Autodesk Fusion 360 part; units mm, degrees
(part 2 of 2)
  line L439 (42.9149, -28.0117) -> (44.5155, -27.6715)
  line L440 (44.5155, -27.6715) -> (44.4279, -27.1608)
  line L441 (44.4279, -27.1608) -> (44.4111, -26.8014)
  line L442 (44.4111, -26.8014) -> (44.4316, -26.4359)
  line L443 (44.4316, -26.4359) -> (44.4774, -26.0666)
  line L444 (44.4774, -26.0666) -> (44.5447, -25.6945)
  line L445 (44.5447, -25.6945) -> (44.6313, -25.3202)
  line L446 (44.6313, -25.3202) -> (44.7358, -24.9442)
  line L447 (44.7358, -24.9442) -> (44.8572, -24.5669)
  line L448 (44.8572, -24.5669) -> (44.9949, -24.1889)
  line L449 (44.9949, -24.1889) -> (45.9888, -24.0844)
  line L450 (45.9888, -24.0844) -> (46.2021, -24.4256)
  line L451 (46.2021, -24.4256) -> (46.3993, -24.7693)
  line L452 (46.3993, -24.7693) -> (46.5797, -25.1154)
  line L453 (46.5797, -25.1154) -> (46.7422, -25.4635)
  line L454 (46.7422, -25.4635) -> (46.8854, -25.8136)
  line L455 (46.8854, -25.8136) -> (47.007, -26.1653)
  line L456 (47.007, -26.1653) -> (47.103, -26.5185)
  line L457 (47.103, -26.5185) -> (47.1613, -26.8736)
  line L458 (47.1613, -26.8736) -> (47.1819, -27.3912)
  line L459 (47.1819, -27.3912) -> (48.8181, -27.3912)
  line L460 (48.8181, -27.3912) -> (48.8387, -26.8736)
  line L461 (48.8387, -26.8736) -> (48.897, -26.5185)
  line L462 (48.897, -26.5185) -> (48.993, -26.1653)
  line L463 (48.993, -26.1653) -> (49.1146, -25.8136)
  line L464 (49.1146, -25.8136) -> (49.2578, -25.4635)
  line L465 (49.2578, -25.4635) -> (49.4203, -25.1154)
  line L466 (49.4203, -25.1154) -> (49.6007, -24.7693)
  line L467 (49.6007, -24.7693) -> (49.7979, -24.4256)
  line L468 (49.7979, -24.4256) -> (50.0112, -24.0844)
  line L469 (50.0112, -24.0844) -> (51.0051, -24.1889)
  line L470 (51.0051, -24.1889) -> (51.1428, -24.5669)
  line L471 (51.1428, -24.5669) -> (51.2642, -24.9442)
  line L472 (51.2642, -24.9442) -> (51.3687, -25.3202)
  line L473 (51.3687, -25.3202) -> (51.4553, -25.6945)
  line L474 (51.4553, -25.6945) -> (51.5226, -26.0666)
  line L475 (51.5226, -26.0666) -> (51.5684, -26.4359)
  line L476 (51.5684, -26.4359) -> (51.5889, -26.8014)
  line L477 (51.5889, -26.8014) -> (51.5721, -27.1608)
  line L478 (51.5721, -27.1608) -> (51.4845, -27.6715)
  line L479 (51.4845, -27.6715) -> (53.0851, -28.0117)
  line L480 (53.0851, -28.0117) -> (53.2128, -27.5096)
  line L481 (53.2128, -27.5096) -> (53.3436, -27.1744)
  line L482 (53.3436, -27.1744) -> (53.511, -26.8488)
  line L483 (53.511, -26.8488) -> (53.703, -26.5301)
  line L484 (53.703, -26.5301) -> (53.9159, -26.2175)
  line L485 (53.9159, -26.2175) -> (54.1473, -25.9108)
  line L486 (54.1473, -25.9108) -> (54.3957, -25.6098)
  line L487 (54.3957, -25.6098) -> (54.66, -25.3145)
  line L488 (54.66, -25.3145) -> (54.9396, -25.0252)
  line L489 (54.9396, -25.0252) -> (55.89, -25.334)
  line L490 (55.89, -25.334) -> (55.9461, -25.7324)
  line L491 (55.9461, -25.7324) -> (55.9864, -26.1266)
  line L492 (55.9864, -26.1266) -> (56.0105, -26.5162)
  line L493 (56.0105, -26.5162) -> (56.0174, -26.9003)
  line L494 (56.0174, -26.9003) -> (56.0058, -27.2783)
  line L495 (56.0058, -27.2783) -> (55.9739, -27.6491)
  line L496 (55.9739, -27.6491) -> (55.9179, -28.0109)
  line L497 (55.9179, -28.0109) -> (55.8267, -28.3589)
  line L498 (55.8267, -28.3589) -> (55.6349, -28.8402)
  line L499 (55.6349, -28.8402) -> (57.1297, -29.5057)
  line L500 (57.1297, -29.5057) -> (57.3591, -29.0412)
  line L501 (57.3591, -29.0412) -> (57.5567, -28.7405)
  line L502 (57.5567, -28.7405) -> (57.7881, -28.4568)
  line L503 (57.7881, -28.4568) -> (58.0423, -28.185)
  line L504 (58.0423, -28.185) -> (58.3154, -27.9235)
  line L505 (58.3154, -27.9235) -> (58.6055, -27.6716)
  line L506 (58.6055, -27.6716) -> (58.9111, -27.4288)
  line L507 (58.9111, -27.4288) -> (59.2311, -27.195)
  line L508 (59.2311, -27.195) -> (59.5647, -26.9701)
  line L509 (59.5647, -26.9701) -> (60.4301, -27.4697)
  line L510 (60.4301, -27.4697) -> (60.4021, -27.8711)
  line L511 (60.4021, -27.8711) -> (60.3597, -28.2651)
  line L512 (60.3597, -28.2651) -> (60.3022, -28.6511)
  line L513 (60.3022, -28.6511) -> (60.229, -29.0283)
  line L514 (60.229, -29.0283) -> (60.1392, -29.3957)
  line L515 (60.1392, -29.3957) -> (60.0308, -29.7517)
  line L516 (60.0308, -29.7517) -> (59.9008, -30.0939)
  line L517 (59.9008, -30.0939) -> (59.7393, -30.4154)
  line L518 (59.7393, -30.4154) -> (59.4516, -30.8463)
  line L519 (59.4516, -30.8463) -> (60.7754, -31.808)
  line L520 (60.7754, -31.808) -> (61.0963, -31.4013)
  line L521 (61.0963, -31.4013) -> (61.3522, -31.1483)
  line L522 (61.3522, -31.1483) -> (61.6375, -30.919)
  line L523 (61.6375, -30.919) -> (61.9426, -30.7059)
  line L524 (61.9426, -30.7059) -> (62.2642, -30.5069)
  line L525 (62.2642, -30.5069) -> (62.6003, -30.3208)
  line L526 (62.6003, -30.3208) -> (62.9497, -30.1469)
  line L527 (62.9497, -30.1469) -> (63.3113, -29.9847)
  line L528 (63.3113, -29.9847) -> (63.6843, -29.834)
  line L529 (63.6843, -29.834) -> (64.427, -30.5027)
  line L530 (64.427, -30.5027) -> (64.3162, -30.8895)
  line L531 (64.3162, -30.8895) -> (64.1927, -31.2661)
  line L532 (64.1927, -31.2661) -> (64.0562, -31.6317)
  line L533 (64.0562, -31.6317) -> (63.9062, -31.9854)
  line L534 (63.9062, -31.9854) -> (63.7419, -32.3261)
  line L535 (63.7419, -32.3261) -> (63.562, -32.6518)
  line L536 (63.562, -32.6518) -> (63.3637, -32.9595)
  line L537 (63.3637, -32.9595) -> (63.1388, -33.2404)
  line L538 (63.1388, -33.2404) -> (62.7679, -33.602)
  line L539 (62.7679, -33.602) -> (63.8627, -34.818)
  line L540 (63.8627, -34.818) -> (64.2612, -34.4869)
  line L541 (64.2612, -34.4869) -> (64.564, -34.2927)
  line L542 (64.564, -34.2927) -> (64.8908, -34.1276)
  line L543 (64.8908, -34.1276) -> (65.2335, -33.9827)
  line L544 (65.2335, -33.9827) -> (65.5895, -33.8549)
  line L545 (65.5895, -33.8549) -> (65.957, -33.7427)
  line L546 (65.957, -33.7427) -> (66.3349, -33.6452)
  line L547 (66.3349, -33.6452) -> (66.7223, -33.5618)
  line L548 (66.7223, -33.5618) -> (67.1185, -33.492)
  line L549 (67.1185, -33.492) -> (67.7059, -34.3005)
  line L550 (67.7059, -34.3005) -> (67.5171, -34.6557)
  line L551 (67.5171, -34.6557) -> (67.318, -34.9984)
  line L552 (67.318, -34.9984) -> (67.1085, -35.3277)
  line L553 (67.1085, -35.3277) -> (66.8883, -35.6425)
  line L554 (66.8883, -35.6425) -> (66.6567, -35.9415)
  line L555 (66.6567, -35.9415) -> (66.413, -36.2227)
  line L556 (66.413, -36.2227) -> (66.155, -36.4825)
  line L557 (66.155, -36.4825) -> (65.8767, -36.7105)
  line L558 (65.8767, -36.7105) -> (65.4386, -36.9871)
  line L559 (65.4386, -36.9871) -> (66.2568, -38.4041)
  line L560 (66.2568, -38.4041) -> (66.7154, -38.1631)
  line L561 (66.7154, -38.1631) -> (67.052, -38.0361)
  line L562 (67.052, -38.0361) -> (67.4059, -37.9425)
  line L563 (67.4059, -37.9425) -> (67.7713, -37.872)
  line L564 (67.7713, -37.872) -> (68.146, -37.821)
  line L565 (68.146, -37.821) -> (68.5288, -37.7877)
  line L566 (68.5288, -37.7877) -> (68.9187, -37.7709)
  line L567 (68.9187, -37.7709) -> (69.315, -37.7698)
  line L568 (69.315, -37.7698) -> (69.7171, -37.784)
  line L569 (69.7171, -37.784) -> (70.1236, -38.6969)
  line L570 (70.1236, -38.6969) -> (69.865, -39.0052)
  line L571 (69.865, -39.0052) -> (69.599, -39.299)
  line L572 (69.599, -39.299) -> (69.3257, -39.5775)
  line L573 (69.3257, -39.5775) -> (69.0448, -39.8396)
  line L574 (69.0448, -39.8396) -> (68.7561, -40.084)
  line L575 (68.7561, -40.084) -> (68.4592, -40.3083)
  line L576 (68.4592, -40.3083) -> (68.1529, -40.5088)
  line L577 (68.1529, -40.5088) -> (67.8333, -40.6739)
  line L578 (67.8333, -40.6739) -> (67.3473, -40.8534)
  line L579 (67.3473, -40.8534) -> (67.8529, -42.4096)
  line L580 (67.8529, -42.4096) -> (68.3516, -42.2692)
  line L581 (68.3516, -42.2692) -> (68.7073, -42.2149)
  line L582 (68.7073, -42.2149) -> (69.0729, -42.197)
  line L583 (69.0729, -42.197) -> (69.445, -42.204)
  line L584 (69.445, -42.204) -> (69.8221, -42.2321)
  line L585 (69.8221, -42.2321) -> (70.2035, -42.2791)
  line L586 (70.2035, -42.2791) -> (70.5883, -42.3437)
  line L587 (70.5883, -42.3437) -> (70.9762, -42.425)
  line L588 (70.9762, -42.425) -> (71.3666, -42.5224)
  line L589 (71.3666, -42.5224) -> (71.5743, -43.5)
  line L590 (71.5743, -43.5) -> (71.2573, -43.7477)
  line L591 (71.2573, -43.7477) -> (70.9361, -43.9798)
  line L592 (70.9361, -43.9798) -> (70.6108, -44.1954)
  line L593 (70.6108, -44.1954) -> (70.2815, -44.3934)
  line L594 (70.2815, -44.3934) -> (69.9484, -44.5724)
  line L595 (69.9484, -44.5724) -> (69.6113, -44.7301)
  line L596 (69.6113, -44.7301) -> (69.27, -44.8625)
  line L597 (69.27, -44.8625) -> (68.923, -44.9576)
  line L598 (68.923, -44.9576) -> (68.4104, -45.0321)
  line L599 (68.4104, -45.0321) -> (68.5814, -46.6595)
extrude "Extrude8'" add sketch "Sketch8 (2)" along normal mid plane 6 bodies 3 in component "Drive roller"
ref_plane "WorkPlane9" through (0, 114.25, 0) normal (0, 1, 0) x (0, 0, 1) in component "Drive roller"
sketch "Sketch9 (2)" plane through (0, 114.25, 0) normal (0, 1, 0) x (1, 0, 0) in component "Drive roller"
  circle A0 centre (68, -48) radius 1.3
extrude "Extrude9'" cut sketch "Sketch9 (2)" along normal mid plane 10.5 bodies 3 in component "Drive roller"
ref_plane "WorkPlane10" through (0, 114.25, 0) normal (0, 1, 0) x (0, 0, 1) in component "Drive roller"
sketch "Sketch10 (2)" plane through (0, 114.25, 0) normal (0, 1, 0) x (1, 0, 0) in component "Drive roller"
  circle A0 centre (48, -68) radius 1.3
extrude "Extrude10'" cut sketch "Sketch10 (2)" along normal mid plane 10.5 bodies 3 in component "Drive roller"
ref_plane "WorkPlane11" through (0, 114.25, 0) normal (0, 1, 0) x (0, 0, 1) in component "Drive roller"
sketch "Sketch11 (2)" plane through (0, 114.25, 0) normal (0, 1, 0) x (1, 0, 0) in component "Drive roller"
  circle A0 centre (28, -48) radius 1.3
extrude "Extrude11'" cut sketch "Sketch11 (2)" along normal mid plane 10.5 bodies 3 in component "Drive roller"
ref_plane "WorkPlane12" through (0, 114.25, 0) normal (0, 1, 0) x (0, 0, 1) in component "Drive roller"
sketch "Sketch12 (2)" plane through (0, 114.25, 0) normal (0, 1, 0) x (1, 0, 0) in component "Drive roller"
  circle A0 centre (48, -28) radius 1.3
extrude "Extrude12'" cut sketch "Sketch12 (2)" along normal mid plane 10.5 bodies 3 in component "Drive roller"
ref_plane "WorkPlane1" through (0, 72, 0) normal (0, 1, 0) x (0, 0, 1) in component "Idle roller"
sketch "Sketch1 (3)" plane through (0, 72, 0) normal (0, 1, 0) x (1, 0, 0) in component "Idle roller"
  circle A0 centre (360, -48) radius 30
extrude "Extrude1''" add sketch "Sketch1 (3)" along normal mid plane 88 separate body makes body 4 in component "Idle roller"
ref_plane "WorkPlane2" through (0, 26.5, 0) normal (0, 1, 0) x (0, 0, 1) in component "Idle roller"
sketch "Sketch2 (3)" plane through (0, 26.5, 0) normal (0, 1, 0) x (1, 0, 0) in component "Idle roller"
  circle A0 centre (360, -48) radius 33
extrude "Extrude2''" add sketch "Sketch2 (3)" along normal mid plane 3 bodies 4 in component "Idle roller"
ref_plane "WorkPlane3" through (0, 117.5, 0) normal (0, 1, 0) x (0, 0, 1) in component "Idle roller"
sketch "Sketch3 (3)" plane through (0, 117.5, 0) normal (0, 1, 0) x (1, 0, 0) in component "Idle roller"
  circle A0 centre (360, -48) radius 33
extrude "Extrude3''" add sketch "Sketch3 (3)" along normal mid plane 3 bodies 4 in component "Idle roller"
ref_plane "WorkPlane4" through (0, 128.75, 0) normal (0, 1, 0) x (0, 0, 1) in component "Idle roller"
sketch "Sketch4 (3)" plane through (0, 128.75, 0) normal (0, 1, 0) x (1, 0, 0) in component "Idle roller"
  circle A0 centre (360, -48) radius 8
extrude "Extrude4''" add sketch "Sketch4 (3)" along normal mid plane 19.5 bodies 4 in component "Idle roller"
ref_plane "WorkPlane5" through (0, 141, 0) normal (0, 1, 0) x (0, 0, 1) in component "Idle roller"
sketch "Sketch5 (3)" plane through (0, 141, 0) normal (0, 1, 0) x (1, 0, 0) in component "Idle roller"
  circle A0 centre (360, -48) radius 4
extrude "Extrude5''" add sketch "Sketch5 (3)" along normal mid plane 5 bodies 4 in component "Idle roller"
ref_plane "WorkPlane6" through (0, 15.25, 0) normal (0, 1, 0) x (0, 0, 1) in component "Idle roller"
sketch "Sketch6 (3)" plane through (0, 15.25, 0) normal (0, 1, 0) x (1, 0, 0) in component "Idle roller"
  circle A0 centre (360, -48) radius 8
extrude "Extrude6''" add sketch "Sketch6 (3)" along normal mid plane 19.5 bodies 4 in component "Idle roller"
ref_plane "WorkPlane7" through (0, 3, 0) normal (0, 1, 0) x (0, 0, 1) in component "Idle roller"
sketch "Sketch7 (3)" plane through (0, 3, 0) normal (0, 1, 0) x (1, 0, 0) in component "Idle roller"
  circle A0 centre (360, -48) radius 4
extrude "Extrude7''" add sketch "Sketch7 (3)" along normal mid plane 5 bodies 4 in component "Idle roller"
ref_plane "WorkPlane1" through (0, -4.5, 0) normal (0, 1, 0) x (0, 0, 1) in component "Pinion"
sketch "Sketch1 (4)" plane through (0, -4.5, 0) normal (0, 1, 0) x (1, 0, 0) in component "Pinion"
  line L0 (91.0629, -46.9226) -> (92.2515, -46.7851)
  line L1 (92.2515, -46.7851) -> (92.5267, -46.7953)
  line L2 (92.5267, -46.7953) -> (92.8056, -46.8416)
  line L3 (92.8056, -46.8416) -> (93.0865, -46.913)
  line L4 (93.0865, -46.913) -> (93.3683, -47.006)
  line L5 (93.3683, -47.006) -> (93.6505, -47.1186)
  line L6 (93.6505, -47.1186) -> (93.9323, -47.2498)
  line L7 (93.9323, -47.2498) -> (94.2132, -47.3986)
  line L8 (94.2132, -47.3986) -> (94.4926, -47.5645)
  line L9 (94.4926, -47.5645) -> (94.4926, -48.4355)
  line L10 (94.4926, -48.4355) -> (94.2132, -48.6014)
  line L11 (94.2132, -48.6014) -> (93.9323, -48.7502)
  line L12 (93.9323, -48.7502) -> (93.6505, -48.8814)
  line L13 (93.6505, -48.8814) -> (93.3683, -48.994)
  line L14 (93.3683, -48.994) -> (93.0865, -49.087)
  line L15 (93.0865, -49.087) -> (92.8056, -49.1584)
  line L16 (92.8056, -49.1584) -> (92.5267, -49.2047)
  line L17 (92.5267, -49.2047) -> (92.2515, -49.2149)
  line L18 (92.2515, -49.2149) -> (91.0629, -49.0774)
  line L19 (91.0629, -49.0774) -> (90.696, -50.8036)
  line L20 (90.696, -50.8036) -> (91.8378, -51.1614)
  line L21 (91.8378, -51.1614) -> (92.085, -51.2827)
  line L22 (92.085, -51.2827) -> (92.321, -51.4384)
  line L23 (92.321, -51.4384) -> (92.5485, -51.6179)
  line L24 (92.5485, -51.6179) -> (92.7682, -51.8175)
  line L25 (92.7682, -51.8175) -> (92.9801, -52.0352)
  line L26 (92.9801, -52.0352) -> (93.1842, -52.2697)
  line L27 (93.1842, -52.2697) -> (93.3803, -52.5198)
  line L28 (93.3803, -52.5198) -> (93.5681, -52.785)
  line L29 (93.5681, -52.785) -> (93.2138, -53.5808)
  line L30 (93.2138, -53.5808) -> (92.8911, -53.6186)
  line L31 (92.8911, -53.6186) -> (92.574, -53.6403)
  line L32 (92.574, -53.6403) -> (92.2632, -53.6455)
  line L33 (92.2632, -53.6455) -> (91.9596, -53.6337)
  line L34 (91.9596, -53.6337) -> (91.6642, -53.604)
  line L35 (91.6642, -53.604) -> (91.3786, -53.555)
  line L36 (91.3786, -53.555) -> (91.105, -53.4838)
  line L37 (91.105, -53.4838) -> (90.8494, -53.3812)
  line L38 (90.8494, -53.3812) -> (89.8195, -52.7722)
  line L39 (89.8195, -52.7722) -> (88.7822, -54.1999)
  line L40 (88.7822, -54.1999) -> (89.6797, -54.9912)
  line L41 (89.6797, -54.9912) -> (89.8563, -55.2026)
  line L42 (89.8563, -55.2026) -> (90.0086, -55.4408)
  line L43 (90.0086, -55.4408) -> (90.1434, -55.6973)
  line L44 (90.1434, -55.6973) -> (90.2629, -55.969)
  line L45 (90.2629, -55.969) -> (90.368, -56.254)
  line L46 (90.368, -56.254) -> (90.4591, -56.5512)
  line L47 (90.4591, -56.5512) -> (90.5364, -56.8596)
  line L48 (90.5364, -56.8596) -> (90.6001, -57.1781)
  line L49 (90.6001, -57.1781) -> (89.9528, -57.761)
  line L50 (89.9528, -57.761) -> (89.6426, -57.6644)
  line L51 (89.6426, -57.6644) -> (89.3441, -57.5552)
  line L52 (89.3441, -57.5552) -> (89.058, -57.4335)
  line L53 (89.058, -57.4335) -> (88.7855, -57.2992)
  line L54 (88.7855, -57.2992) -> (88.5278, -57.152)
  line L55 (88.5278, -57.152) -> (88.2868, -56.9911)
  line L56 (88.2868, -56.9911) -> (88.0658, -56.8148)
  line L57 (88.0658, -56.8148) -> (87.874, -56.6171)
  line L58 (87.874, -56.6171) -> (87.1809, -55.6418)
  line L59 (87.1809, -55.6418) -> (85.6525, -56.5241)
  line L60 (85.6525, -56.5241) -> (86.1506, -57.6121)
  line L61 (86.1506, -57.6121) -> (86.2259, -57.877)
  line L62 (86.2259, -57.877) -> (86.2681, -58.1565)
  line L63 (86.2681, -58.1565) -> (86.287, -58.4457)
  line L64 (86.287, -58.4457) -> (86.2856, -58.7425)
  line L65 (86.2856, -58.7425) -> (86.2657, -59.0457)
  line L66 (86.2657, -59.0457) -> (86.228, -59.3542)
  line L67 (86.228, -59.3542) -> (86.1733, -59.6674)
  line L68 (86.1733, -59.6674) -> (86.1019, -59.9843)
  line L69 (86.1019, -59.9843) -> (85.2734, -60.2535)
  line L70 (85.2734, -60.2535) -> (85.0294, -60.039)
  line L71 (85.0294, -60.039) -> (84.8011, -59.8179)
  line L72 (84.8011, -59.8179) -> (84.5892, -59.5904)
  line L73 (84.5892, -59.5904) -> (84.3949, -59.3569)
  line L74 (84.3949, -59.3569) -> (84.2193, -59.1175)
  line L75 (84.2193, -59.1175) -> (84.0646, -58.8725)
  line L76 (84.0646, -58.8725) -> (83.9344, -58.6215)
  line L77 (83.9344, -58.6215) -> (83.8397, -58.363)
  line L78 (83.8397, -58.363) -> (83.6031, -57.19)
  line L79 (83.6031, -57.19) -> (81.8481, -57.3745)
  line L80 (81.8481, -57.3745) -> (81.8606, -58.571)
  line L81 (81.8606, -58.571) -> (81.8216, -58.8436)
  line L82 (81.8216, -58.8436) -> (81.7465, -59.1162)
  line L83 (81.7465, -59.1162) -> (81.6461, -59.388)
  line L84 (81.6461, -59.388) -> (81.5241, -59.6586)
  line L85 (81.5241, -59.6586) -> (81.3826, -59.9274)
  line L86 (81.3826, -59.9274) -> (81.2227, -60.194)
  line L87 (81.2227, -60.194) -> (81.0453, -60.4578)
  line L88 (81.0453, -60.4578) -> (80.8512, -60.7183)
  line L89 (80.8512, -60.7183) -> (79.9849, -60.6272)
  line L90 (79.9849, -60.6272) -> (79.8492, -60.3321)
  line L91 (79.8492, -60.3321) -> (79.7305, -60.0372)
  line L92 (79.7305, -60.0372) -> (79.6295, -59.7432)
  line L93 (79.6295, -59.7432) -> (79.547, -59.4508)
  line L94 (79.547, -59.4508) -> (79.4839, -59.1607)
  line L95 (79.4839, -59.1607) -> (79.4423, -58.874)
  line L96 (79.4423, -58.874) -> (79.4254, -58.5918)
  line L97 (79.4254, -58.5918) -> (79.444, -58.317)
  line L98 (79.444, -58.317) -> (79.705, -57.1492)
  line L99 (79.705, -57.1492) -> (78.0266, -56.6039)
  line L100 (78.0266, -56.6039) -> (77.5514, -57.702)
  line L101 (77.5514, -57.702) -> (77.405, -57.9353)
  line L102 (77.405, -57.9353) -> (77.2254, -58.1537)
  line L103 (77.2254, -58.1537) -> (77.0232, -58.3612)
  line L104 (77.0232, -58.3612) -> (76.8017, -58.5588)
  line L105 (76.8017, -58.5588) -> (76.563, -58.7468)
  line L106 (76.563, -58.7468) -> (76.3085, -58.9253)
  line L107 (76.3085, -58.9253) -> (76.0392, -59.0941)
  line L108 (76.0392, -59.0941) -> (75.7559, -59.2532)
  line L109 (75.7559, -59.2532) -> (75.0015, -58.8176)
  line L110 (75.0015, -58.8176) -> (74.9976, -58.4927)
  line L111 (74.9976, -58.4927) -> (75.0092, -58.1751)
  line L112 (75.0092, -58.1751) -> (75.0365, -57.8654)
  line L113 (75.0365, -57.8654) -> (75.08, -57.5647)
  line L114 (75.08, -57.5647) -> (75.1404, -57.2742)
  line L115 (75.1404, -57.2742) -> (75.2189, -56.9952)
  line L116 (75.2189, -56.9952) -> (75.3183, -56.7306)
  line L117 (75.3183, -56.7306) -> (75.4471, -56.4871)
  line L118 (75.4471, -56.4871) -> (76.1605, -55.5265)
  line L119 (76.1605, -55.5265) -> (74.849, -54.3456)
  line L120 (74.849, -54.3456) -> (73.9682, -55.1555)
  line L121 (73.9682, -55.1555) -> (73.7396, -55.309)
  line L122 (73.7396, -55.309) -> (73.4867, -55.4355)
  line L123 (73.4867, -55.4355) -> (73.2175, -55.5428)
  line L124 (73.2175, -55.5428) -> (72.9349, -55.6333)
  line L125 (72.9349, -55.6333) -> (72.6404, -55.708)
  line L126 (72.6404, -55.708) -> (72.3353, -55.7675)
  line L127 (72.3353, -55.7675) -> (72.0206, -55.8122)
  line L128 (72.0206, -55.8122) -> (71.6971, -55.8422)
  line L129 (71.6971, -55.8422) -> (71.185, -55.1375)
  line L130 (71.185, -55.1375) -> (71.3136, -54.8391)
  line L131 (71.3136, -54.8391) -> (71.4534, -54.5537)
  line L132 (71.4534, -54.5537) -> (71.6043, -54.2819)
  line L133 (71.6043, -54.2819) -> (71.7663, -54.0249)
  line L134 (71.7663, -54.0249) -> (71.9397, -53.784)
  line L135 (71.9397, -53.784) -> (72.1249, -53.5611)
  line L136 (72.1249, -53.5611) -> (72.3233, -53.3598)
  line L137 (72.3233, -53.3598) -> (72.54, -53.1897)
  line L138 (72.54, -53.1897) -> (73.5824, -52.6023)
  line L139 (73.5824, -52.6023) -> (72.8646, -50.9901)
  line L140 (72.8646, -50.9901) -> (71.7306, -51.3718)
  line L141 (71.7306, -51.3718) -> (71.4592, -51.419)
  line L142 (71.4592, -51.419) -> (71.1768, -51.4317)
  line L143 (71.1768, -51.4317) -> (70.8873, -51.4203)
  line L144 (70.8873, -51.4203) -> (70.5922, -51.3879)
  line L145 (70.5922, -51.3879) -> (70.2928, -51.3363)
  line L146 (70.2928, -51.3363) -> (69.9899, -51.2666)
  line L147 (69.9899, -51.2666) -> (69.6842, -51.1795)
  line L148 (69.6842, -51.1795) -> (69.3765, -51.0754)
  line L149 (69.3765, -51.0754) -> (69.1953, -50.2233)
  line L150 (69.1953, -50.2233) -> (69.4341, -50.003)
  line L151 (69.4341, -50.003) -> (69.6779, -49.799)
  line L152 (69.6779, -49.799) -> (69.9263, -49.6122)
  line L153 (69.9263, -49.6122) -> (70.1789, -49.4433)
  line L154 (70.1789, -49.4433) -> (70.4353, -49.2937)
  line L155 (70.4353, -49.2937) -> (70.6951, -49.1655)
  line L156 (70.6951, -49.1655) -> (70.9583, -49.0622)
  line L157 (70.9583, -49.0622) -> (71.2254, -48.995)
  line L158 (71.2254, -48.995) -> (72.4166, -48.8824)
  line L159 (72.4166, -48.8824) -> (72.4166, -47.1176)
  line L160 (72.4166, -47.1176) -> (71.2254, -47.005)
  line L161 (71.2254, -47.005) -> (70.9583, -46.9378)
  line L162 (70.9583, -46.9378) -> (70.6951, -46.8345)
  line L163 (70.6951, -46.8345) -> (70.4353, -46.7063)
  line L164 (70.4353, -46.7063) -> (70.1789, -46.5567)
  line L165 (70.1789, -46.5567) -> (69.9263, -46.3878)
  line L166 (69.9263, -46.3878) -> (69.6779, -46.201)
  line L167 (69.6779, -46.201) -> (69.4341, -45.997)
  line L168 (69.4341, -45.997) -> (69.1953, -45.7767)
  line L169 (69.1953, -45.7767) -> (69.3765, -44.9246)
  line L170 (69.3765, -44.9246) -> (69.6842, -44.8205)
  line L171 (69.6842, -44.8205) -> (69.9899, -44.7334)
  line L172 (69.9899, -44.7334) -> (70.2928, -44.6637)
  line L173 (70.2928, -44.6637) -> (70.5922, -44.6121)
  line L174 (70.5922, -44.6121) -> (70.8873, -44.5797)
  line L175 (70.8873, -44.5797) -> (71.1768, -44.5683)
  line L176 (71.1768, -44.5683) -> (71.4592, -44.581)
  line L177 (71.4592, -44.581) -> (71.7306, -44.6282)
  line L178 (71.7306, -44.6282) -> (72.8646, -45.0099)
  line L179 (72.8646, -45.0099) -> (73.5824, -43.3977)
  line L180 (73.5824, -43.3977) -> (72.54, -42.8103)
  line L181 (72.54, -42.8103) -> (72.3233, -42.6402)
  line L182 (72.3233, -42.6402) -> (72.1249, -42.4389)
  line L183 (72.1249, -42.4389) -> (71.9397, -42.216)
  line L184 (71.9397, -42.216) -> (71.7663, -41.9751)
  line L185 (71.7663, -41.9751) -> (71.6043, -41.7181)
  line L186 (71.6043, -41.7181) -> (71.4534, -41.4463)
  line L187 (71.4534, -41.4463) -> (71.3136, -41.1609)
  line L188 (71.3136, -41.1609) -> (71.185, -40.8625)
  line L189 (71.185, -40.8625) -> (71.6971, -40.1578)
  line L190 (71.6971, -40.1578) -> (72.0206, -40.1878)
  line L191 (72.0206, -40.1878) -> (72.3353, -40.2325)
  line L192 (72.3353, -40.2325) -> (72.6404, -40.292)
  line L193 (72.6404, -40.292) -> (72.9349, -40.3667)
  line L194 (72.9349, -40.3667) -> (73.2175, -40.4572)
  line L195 (73.2175, -40.4572) -> (73.4867, -40.5645)
  line L196 (73.4867, -40.5645) -> (73.7396, -40.691)
  line L197 (73.7396, -40.691) -> (73.9682, -40.8445)
  line L198 (73.9682, -40.8445) -> (74.849, -41.6544)
  line L199 (74.849, -41.6544) -> (76.1605, -40.4735)
  line L200 (76.1605, -40.4735) -> (75.4471, -39.5129)
  line L201 (75.4471, -39.5129) -> (75.3183, -39.2694)
  line L202 (75.3183, -39.2694) -> (75.2189, -39.0048)
  line L203 (75.2189, -39.0048) -> (75.1404, -38.7258)
  line L204 (75.1404, -38.7258) -> (75.08, -38.4353)
  line L205 (75.08, -38.4353) -> (75.0365, -38.1346)
  line L206 (75.0365, -38.1346) -> (75.0092, -37.8249)
  line L207 (75.0092, -37.8249) -> (74.9976, -37.5073)
  line L208 (74.9976, -37.5073) -> (75.0015, -37.1824)
  line L209 (75.0015, -37.1824) -> (75.7559, -36.7468)
  line L210 (75.7559, -36.7468) -> (76.0392, -36.9059)
  line L211 (76.0392, -36.9059) -> (76.3085, -37.0747)
  line L212 (76.3085, -37.0747) -> (76.563, -37.2532)
  line L213 (76.563, -37.2532) -> (76.8017, -37.4412)
  line L214 (76.8017, -37.4412) -> (77.0232, -37.6388)
  line L215 (77.0232, -37.6388) -> (77.2254, -37.8463)
  line L216 (77.2254, -37.8463) -> (77.405, -38.0647)
  line L217 (77.405, -38.0647) -> (77.5514, -38.298)
  line L218 (77.5514, -38.298) -> (78.0266, -39.3961)
  line L219 (78.0266, -39.3961) -> (79.705, -38.8508)
  line L220 (79.705, -38.8508) -> (79.444, -37.683)
  line L221 (79.444, -37.683) -> (79.4254, -37.4082)
  line L222 (79.4254, -37.4082) -> (79.4423, -37.126)
  line L223 (79.4423, -37.126) -> (79.4839, -36.8393)
  line L224 (79.4839, -36.8393) -> (79.547, -36.5492)
  line L225 (79.547, -36.5492) -> (79.6295, -36.2568)
  line L226 (79.6295, -36.2568) -> (79.7305, -35.9628)
  line L227 (79.7305, -35.9628) -> (79.8492, -35.6679)
  line L228 (79.8492, -35.6679) -> (79.9849, -35.3728)
  line L229 (79.9849, -35.3728) -> (80.8512, -35.2817)
  line L230 (80.8512, -35.2817) -> (81.0453, -35.5422)
  line L231 (81.0453, -35.5422) -> (81.2227, -35.806)
  line L232 (81.2227, -35.806) -> (81.3826, -36.0726)
  line L233 (81.3826, -36.0726) -> (81.5241, -36.3414)
  line L234 (81.5241, -36.3414) -> (81.6461, -36.612)
  line L235 (81.6461, -36.612) -> (81.7465, -36.8838)
  line L236 (81.7465, -36.8838) -> (81.8216, -37.1564)
  line L237 (81.8216, -37.1564) -> (81.8606, -37.429)
  line L238 (81.8606, -37.429) -> (81.8481, -38.6255)
  line L239 (81.8481, -38.6255) -> (83.6031, -38.81)
  line L240 (83.6031, -38.81) -> (83.8397, -37.637)
  line L241 (83.8397, -37.637) -> (83.9344, -37.3785)
  line L242 (83.9344, -37.3785) -> (84.0646, -37.1275)
  line L243 (84.0646, -37.1275) -> (84.2193, -36.8825)
  line L244 (84.2193, -36.8825) -> (84.3949, -36.6431)
  line L245 (84.3949, -36.6431) -> (84.5892, -36.4096)
  line L246 (84.5892, -36.4096) -> (84.8011, -36.1821)
  line L247 (84.8011, -36.1821) -> (85.0294, -35.961)
  line L248 (85.0294, -35.961) -> (85.2734, -35.7465)
  line L249 (85.2734, -35.7465) -> (86.1019, -36.0157)
  line L250 (86.1019, -36.0157) -> (86.1733, -36.3326)
  line L251 (86.1733, -36.3326) -> (86.228, -36.6458)
  line L252 (86.228, -36.6458) -> (86.2657, -36.9543)
  line L253 (86.2657, -36.9543) -> (86.2856, -37.2575)
  line L254 (86.2856, -37.2575) -> (86.287, -37.5543)
  line L255 (86.287, -37.5543) -> (86.2681, -37.8435)
  line L256 (86.2681, -37.8435) -> (86.2259, -38.123)
  line L257 (86.2259, -38.123) -> (86.1506, -38.3879)
  line L258 (86.1506, -38.3879) -> (85.6525, -39.4759)
  line L259 (85.6525, -39.4759) -> (87.1809, -40.3582)
  line L260 (87.1809, -40.3582) -> (87.874, -39.3829)
  line L261 (87.874, -39.3829) -> (88.0658, -39.1852)
  line L262 (88.0658, -39.1852) -> (88.2868, -39.0089)
  line L263 (88.2868, -39.0089) -> (88.5278, -38.848)
  line L264 (88.5278, -38.848) -> (88.7855, -38.7008)
  line L265 (88.7855, -38.7008) -> (89.058, -38.5665)
  line L266 (89.058, -38.5665) -> (89.3441, -38.4448)
  line L267 (89.3441, -38.4448) -> (89.6426, -38.3356)
  line L268 (89.6426, -38.3356) -> (89.9528, -38.239)
  line L269 (89.9528, -38.239) -> (90.6001, -38.8219)
  line L270 (90.6001, -38.8219) -> (90.5364, -39.1404)
  line L271 (90.5364, -39.1404) -> (90.4591, -39.4488)
  line L272 (90.4591, -39.4488) -> (90.368, -39.746)
  line L273 (90.368, -39.746) -> (90.2629, -40.031)
  line L274 (90.2629, -40.031) -> (90.1434, -40.3027)
  line L275 (90.1434, -40.3027) -> (90.0086, -40.5592)
  line L276 (90.0086, -40.5592) -> (89.8563, -40.7974)
  line L277 (89.8563, -40.7974) -> (89.6797, -41.0088)
  line L278 (89.6797, -41.0088) -> (88.7822, -41.8001)
  line L279 (88.7822, -41.8001) -> (89.8195, -43.2278)
  line L280 (89.8195, -43.2278) -> (90.8494, -42.6188)
  line L281 (90.8494, -42.6188) -> (91.105, -42.5162)
  line L282 (91.105, -42.5162) -> (91.3786, -42.445)
  line L283 (91.3786, -42.445) -> (91.6642, -42.396)
  line L284 (91.6642, -42.396) -> (91.9596, -42.3663)
  line L285 (91.9596, -42.3663) -> (92.2632, -42.3545)
  line L286 (92.2632, -42.3545) -> (92.574, -42.3597)
  line L287 (92.574, -42.3597) -> (92.8911, -42.3814)
  line L288 (92.8911, -42.3814) -> (93.2138, -42.4192)
  line L289 (93.2138, -42.4192) -> (93.5681, -43.215)
  line L290 (93.5681, -43.215) -> (93.3803, -43.4802)
  line L291 (93.3803, -43.4802) -> (93.1842, -43.7303)
  line L292 (93.1842, -43.7303) -> (92.9801, -43.9648)
  line L293 (92.9801, -43.9648) -> (92.7682, -44.1825)
  line L294 (92.7682, -44.1825) -> (92.5485, -44.3821)
  line L295 (92.5485, -44.3821) -> (92.321, -44.5616)
  line L296 (92.321, -44.5616) -> (92.085, -44.7173)
  line L297 (92.085, -44.7173) -> (91.8378, -44.8386)
  line L298 (91.8378, -44.8386) -> (90.696, -45.1964)
  line L299 (90.696, -45.1964) -> (91.0629, -46.9226)
extrude "Extrude1'''" add sketch "Sketch1 (4)" along normal mid plane 6 separate body makes body 5 in component "Pinion"
ref_plane "WorkPlane2" through (0, -4.5, 0) normal (0, 1, 0) x (0, 0, 1) in component "Pinion"
sketch "Sketch2 (4)" plane through (0, -4.5, 0) normal (0, 1, 0) x (1, 0, 0) in component "Pinion"
  circle A0 centre (81.75, -48) radius 2.8
extrude "Extrude2'''" cut sketch "Sketch2 (4)" along normal mid plane 7 bodies 5 in component "Pinion"
ref_plane "WorkPlane3" through (0, -4.5, 0) normal (0, 1, 0) x (0, 0, 1) in component "Pinion"
sketch "Sketch3 (4)" plane through (0, -4.5, 0) normal (0, 1, 0) x (1, 0, 0) in component "Pinion"
  line L0 (78.65, -49.925) -> (84.85, -49.925)
  line L1 (84.85, -49.925) -> (84.85, -51.1)
  line L2 (84.85, -51.1) -> (78.65, -51.1)
  line L3 (78.65, -51.1) -> (78.65, -49.925)
extrude "Extrude3'''" add sketch "Sketch3 (4)" along normal mid plane 6 bodies 5 in component "Pinion"
ref_plane "WorkPlane4" through (0, -4.5, 0) normal (0, 1, 0) x (0, 0, 1) in component "Pinion"
sketch "Sketch4 (4)" plane through (0, -4.5, 0) normal (0, 1, 0) x (1, 0, 0) in component "Pinion"
  line L0 (78.65, -44.9) -> (84.85, -44.9)
  line L1 (84.85, -44.9) -> (84.85, -46.075)
  line L2 (84.85, -46.075) -> (78.65, -46.075)
  line L3 (78.65, -46.075) -> (78.65, -44.9)
extrude "Extrude4'''" add sketch "Sketch4 (4)" along normal mid plane 6 bodies 5 in component "Pinion"
ref_plane "WorkPlane1" through (0, 72, 0) normal (0, 1, 0) x (0, 0, 1) in component "Belt (reference)"
sketch "Sketch1 (5)" plane through (0, 72, 0) normal (0, 1, 0) x (1, 0, 0) in component "Belt (reference)"
  circle A0 centre (48, -48) radius 31
extrude "Extrude1''''" add sketch "Sketch1 (5)" along normal mid plane 80 separate body makes body 6 in component "Belt (reference)"
ref_plane "WorkPlane2" through (0, 72, 0) normal (0, 1, 0) x (0, 0, 1) in component "Belt (reference)"
sketch "Sketch2 (5)" plane through (0, 72, 0) normal (0, 1, 0) x (1, 0, 0) in component "Belt (reference)"
  circle A0 centre (360, -48) radius 31
extrude "Extrude2''''" add sketch "Sketch2 (5)" along normal mid plane 80 bodies 6 makes body 7 in component "Belt (reference)"
ref_plane "WorkPlane3" through (0, 72, 0) normal (0, 1, 0) x (0, 0, 1) in component "Belt (reference)"
sketch "Sketch3 (5)" plane through (0, 72, 0) normal (0, 1, 0) x (1, 0, 0) in component "Belt (reference)"
  line L0 (48, -17) -> (360, -17)
  line L1 (360, -17) -> (360, -79)
  line L2 (360, -79) -> (48, -79)
  line L3 (48, -79) -> (48, -17)
extrude "Extrude3''''" add sketch "Sketch3 (5)" along normal mid plane 80 bodies 6 in component "Belt (reference)"
ref_plane "WorkPlane4" through (0, 72, 0) normal (0, 1, 0) x (0, 0, 1) in component "Belt (reference)"
sketch "Sketch4 (5)" plane through (0, 72, 0) normal (0, 1, 0) x (1, 0, 0) in component "Belt (reference)"
  circle A0 centre (48, -48) radius 30
extrude "Extrude4''''" cut sketch "Sketch4 (5)" along normal mid plane 82 bodies 6 in component "Belt (reference)"
ref_plane "WorkPlane5" through (0, 72, 0) normal (0, 1, 0) x (0, 0, 1) in component "Belt (reference)"
sketch "Sketch5 (4)" plane through (0, 72, 0) normal (0, 1, 0) x (1, 0, 0) in component "Belt (reference)"
  circle A0 centre (360, -48) radius 30
extrude "Extrude5'''" cut sketch "Sketch5 (4)" along normal mid plane 82 bodies 6 in component "Belt (reference)"
ref_plane "WorkPlane6" through (0, 72, 0) normal (0, 1, 0) x (0, 0, 1) in component "Belt (reference)"
sketch "Sketch6 (4)" plane through (0, 72, 0) normal (0, 1, 0) x (1, 0, 0) in component "Belt (reference)"
  line L0 (48, -18) -> (360, -18)
  line L1 (360, -18) -> (360, -78)
  line L2 (360, -78) -> (48, -78)
  line L3 (48, -78) -> (48, -18)
extrude "Extrude6'''" cut sketch "Sketch6 (4)" along normal mid plane 82 bodies 6 in component "Belt (reference)"
ref_plane "WorkPlane1" through (0, 0, 5) normal (0, 0, 1) x (1, 0, 0) in component "Motor bracket"
sketch "Sketch1 (6)" plane through (0, 0, 5) normal (0, 0, 1) x (1, 0, 0) in component "Motor bracket"
  line L0 (67.45, -39.1) -> (118.75, -39.1)
  line L1 (118.75, -39.1) -> (118.75, -9.5)
  line L2 (118.75, -9.5) -> (67.45, -9.5)
  line L3 (67.45, -9.5) -> (67.45, -39.1)
extrude "Extrude1'''''" add sketch "Sketch1 (6)" along normal blind 3 separate body makes body 8 in component "Motor bracket"
ref_plane "WorkPlane2" through (0, 0, 7.99) normal (0, 0, 1) x (1, 0, 0) in component "Motor bracket"
sketch "Sketch2 (6)" plane through (0, 0, 7.99) normal (0, 0, 1) x (1, 0, 0) in component "Motor bracket"
  line L0 (70.45, -28.11) -> (118.75, -28.11)
  line L1 (118.75, -28.11) -> (118.75, -9.5)
  line L2 (118.75, -9.5) -> (70.45, -9.5)
  line L3 (70.45, -9.5) -> (70.45, -28.11)
extrude "Extrude2'''''" add sketch "Sketch2 (6)" along normal blind 28.46 bodies 8 in component "Motor bracket"
ref_plane "WorkPlane3" through (0, 0, 7.99) normal (0, 0, 1) x (1, 0, 0) in component "Motor bracket"
sketch "Sketch3 (6)" plane through (0, 0, 7.99) normal (0, 0, 1) x (1, 0, 0) in component "Motor bracket"
  line L0 (67.45, -31.1) -> (70.45, -31.1)
  line L1 (70.45, -31.1) -> (70.45, -9.5)
  line L2 (70.45, -9.5) -> (67.45, -9.5)
  line L3 (67.45, -9.5) -> (67.45, -31.1)
extrude "Extrude3'''''" add sketch "Sketch3 (6)" along normal blind 38.76 bodies 8 in component "Motor bracket"
ref_plane "WorkPlane4" through (0, 0, 7.99) normal (0, 0, 1) x (1, 0, 0) in component "Motor bracket"
sketch "Sketch4 (6)" plane through (0, 0, 7.99) normal (0, 0, 1) x (1, 0, 0) in component "Motor bracket"
  line L0 (67.45, -31.1) -> (118.75, -31.1)
  line L1 (118.75, -31.1) -> (118.75, -28.1)
  line L2 (118.75, -28.1) -> (67.45, -28.1)
  line L3 (67.45, -28.1) -> (67.45, -31.1)
extrude "Extrude4'''''" add sketch "Sketch4 (6)" along normal blind 42.76 bodies 8 in component "Motor bracket"
ref_plane "WorkPlane5" through (0, -29.6, 0) normal (0, 1, 0) x (0, 0, 1) in component "Motor bracket"
sketch "Sketch5 (5)" plane through (0, -29.6, 0) normal (0, 1, 0) x (1, 0, 0) in component "Motor bracket"
  circle A0 centre (81.75, -48) radius 4.5
extrude "Extrude5''''" cut sketch "Sketch5 (5)" along normal mid plane 4 bodies 8 in component "Motor bracket"
ref_plane "WorkPlane6" through (0, 0, 4.5) normal (0, 0, 1) x (1, 0, 0) in component "Motor bracket"
sketch "Sketch6 (5)" plane through (0, 0, 4.5) normal (0, 0, 1) x (1, 0, 0) in component "Motor bracket"
  circle A0 centre (74.75, -35.1) radius 1.7
extrude "Extrude6''''" cut sketch "Sketch6 (5)" along normal blind 4 bodies 8 in component "Motor bracket"
ref_plane "WorkPlane7" through (0, 0, 4.5) normal (0, 0, 1) x (1, 0, 0) in component "Motor bracket"
sketch "Sketch7 (4)" plane through (0, 0, 4.5) normal (0, 0, 1) x (1, 0, 0) in component "Motor bracket"
  circle A0 centre (114.75, -35.1) radius 1.7
extrude "Extrude7'''" cut sketch "Sketch7 (4)" along normal blind 4 bodies 8 in component "Motor bracket"
ref_plane "WorkPlane8" through (0, -20.3, 0) normal (0, 1, 0) x (0, 0, 1) in component "Motor bracket"
sketch "Sketch8 (3)" plane through (0, -20.3, 0) normal (0, 1, 0) x (1, 0, 0) in component "Motor bracket"
  line L0 (98.75, -33.65) -> (102.75, -33.65)
  line L1 (102.75, -33.65) -> (102.75, -35.65)
  line L2 (102.75, -35.65) -> (98.75, -35.65)
  line L3 (98.75, -35.65) -> (98.75, -33.65)
extrude "Extrude8''" cut sketch "Sketch8 (3)" along normal mid plane 22.6 bodies 8 in component "Motor bracket"
ref_plane "WorkPlane9" through (0, -20.3, 0) normal (0, 1, 0) x (0, 0, 1) in component "Motor bracket"
sketch "Sketch9 (3)" plane through (0, -20.3, 0) normal (0, 1, 0) x (1, 0, 0) in component "Motor bracket"
  line L0 (110.75, -33.65) -> (114.75, -33.65)
  line L1 (114.75, -33.65) -> (114.75, -35.65)
  line L2 (114.75, -35.65) -> (110.75, -35.65)
  line L3 (110.75, -35.65) -> (110.75, -33.65)
extrude "Extrude9''" cut sketch "Sketch9 (3)" along normal mid plane 22.6 bodies 8 in component "Motor bracket"
component "Frame" placed x (1, 0, 0) y (0, 1, 0) z (0, 0, 1) at (0, 0, 0)
component "Drive roller" placed x (1, 0, 0) y (0, 1, 0) z (0, 0, 1) at (0, 0, 0)
component "Idle roller" placed x (1, 0, 0) y (0, 1, 0) z (0, 0, 1) at (0, 0, 0)
component "Pinion" placed x (1, 0, 0) y (0, 1, 0) z (0, 0, 1) at (0, 0, 0)
component "Belt (reference)" placed x (1, 0, 0) y (0, 1, 0) z (0, 0, 1) at (0, 0, 0)
component "Motor bracket" placed x (1, 0, 0) y (0, 1, 0) z (0, 0, 1) at (0, 0, 0)
named bodies: "Frame half A (motor end)", "Frame half B (idle end)", "Drive roller (with gear)", "Idle roller", "Pinion", "Belt (reference)", "Motor bracket"
